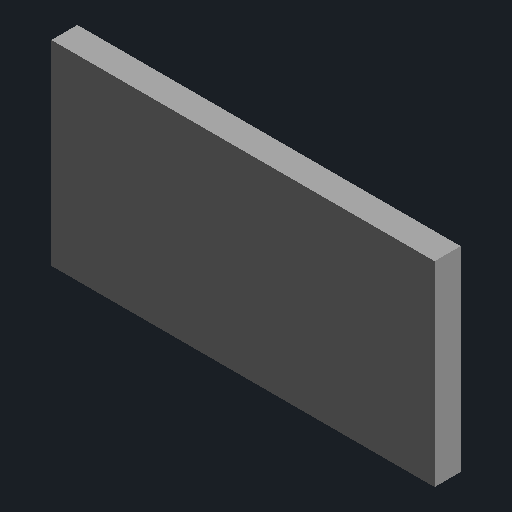
# Autodesk Inventor part: Fichas_pines_ESP32
Saved by Autodesk Inventor 2027 (Build 310192060, 192F)
## iProperties
Part Number: Fichas_pines_ESP32
Material: Genérico
Document SubType Name: Modelado
Designer: rodri
Appearance: Por defecto
Author: rodri
Autodesk Inventor part; units mm, degrees
sketch "Boceto1" plane through (0, 0, 0) normal (0, 0, 1) x (1, 0, 0)
  line L0 (0, 0) -> (38.2, 0)
  line L1 (38.2, 0) -> (38.2, 19.5)
  line L2 (38.2, 19.5) -> (0, 19.5)
  line L3 (0, 19.5) -> (0, 0)
  constraints: 8 end point, 2 parallel, 1 horizontal, 1 perpendicular
extrude "Extrusión1" add sketch "Boceto1" along normal blind 2.6
ref_plane "Plano de trabajo1" through (0, 0, 0) normal (0, 1, 0) x (0, 0, 1)
ref_plane "Plano de trabajo2" through (0, 0, 0) normal (1, 0, 0) x (0, 0, -1)
ref_plane "Plano de trabajo3" through (0, 0, 0) normal (0, 1, 0) x (0, 0, 1)
ref_plane "Plano de trabajo4" through (0, 0, 0) normal (1, 0, 0) x (0, 0, -1)
ref_plane "Plano de trabajo5" through (0, 0, 0) normal (0, 1, 0) x (0, 0, 1)
ref_plane "Plano de trabajo6" through (0, 0, 0) normal (1, 0, 0) x (0, 0, -1)
ref_plane "Plano de trabajo7" through (0, 0, 0) normal (0, 1, 0) x (0, 0, 1)
ref_plane "Plano de trabajo8" through (0, 0, 0) normal (1, 0, 0) x (0, 0, -1)
ref_plane "Plano de trabajo9" through (0, 0, 0) normal (0, 1, 0) x (0, 0, 1)
ref_plane "Plano de trabajo10" through (0, 0, 0) normal (1, 0, 0) x (0, 0, -1)
ref_plane "Plano de trabajo11" through (0, 0, 0) normal (0, 1, 0) x (0, 0, 1)
ref_plane "Plano de trabajo12" through (0, 0, 0) normal (1, 0, 0) x (0, 0, -1)
ref_plane "Plano de trabajo13" through (0, 0, 0) normal (0, 1, 0) x (0, 0, 1)
ref_plane "Plano de trabajo14" through (0, 0, 0) normal (1, 0, 0) x (0, 0, -1)
ref_plane "Plano de trabajo15" through (0, 0, 0) normal (0, 1, 0) x (0, 0, 1)
ref_plane "Plano de trabajo16" through (0, 0, 0) normal (1, 0, 0) x (0, 0, -1)
ref_plane "Plano de trabajo17" through (0, 0, 0) normal (0, 1, 0) x (0, 0, 1)
ref_plane "Plano de trabajo18" through (0, 0, 0) normal (1, 0, 0) x (0, 0, -1)
ref_plane "Plano de trabajo19" through (0, 0, 0) normal (0, 1, 0) x (0, 0, 1)
ref_plane "Plano de trabajo20" through (0, 0, 0) normal (1, 0, 0) x (0, 0, -1)
ref_plane "Plano de trabajo21" through (0, 0, 0) normal (0, 1, 0) x (0, 0, 1)
ref_plane "Plano de trabajo22" through (0, 0, 0) normal (1, 0, 0) x (0, 0, -1)
ref_plane "Plano de trabajo23" through (0, 0, 0) normal (0, 1, 0) x (0, 0, 1)
ref_plane "Plano de trabajo24" through (0, 0, 0) normal (1, 0, 0) x (0, 0, -1)
ref_plane "Plano de trabajo25" through (0, 0, 0) normal (0, 1, 0) x (0, 0, 1)
ref_plane "Plano de trabajo26" through (0, 0, 0) normal (1, 0, 0) x (0, 0, -1)
ref_plane "Plano de trabajo27" through (0, 0, 0) normal (0, 1, 0) x (0, 0, 1)
ref_plane "Plano de trabajo28" through (0, 0, 0) normal (1, 0, 0) x (0, 0, -1)
ref_plane "Plano de trabajo29" through (0, 0, 0) normal (0, 1, 0) x (0, 0, 1)
ref_plane "Plano de trabajo30" through (0, 0, 0) normal (1, 0, 0) x (0, 0, -1)
ref_plane "Plano de trabajo31" through (0, 0, 0) normal (0, 1, 0) x (0, 0, 1)
ref_plane "Plano de trabajo32" through (0, 0, 0) normal (1, 0, 0) x (0, 0, -1)
ref_plane "Plano de trabajo33" through (0, 0, 0) normal (0, 1, 0) x (0, 0, 1)
ref_plane "Plano de trabajo34" through (0, 0, 0) normal (1, 0, 0) x (0, 0, -1)
ref_plane "Plano de trabajo35" through (0, 0, 0) normal (0, 1, 0) x (0, 0, 1)
ref_plane "Plano de trabajo36" through (0, 0, 0) normal (1, 0, 0) x (0, 0, -1)
ref_plane "Plano de trabajo37" through (0, 0, 0) normal (0, 1, 0) x (0, 0, 1)
ref_plane "Plano de trabajo38" through (0, 0, 0) normal (1, 0, 0) x (0, 0, -1)
